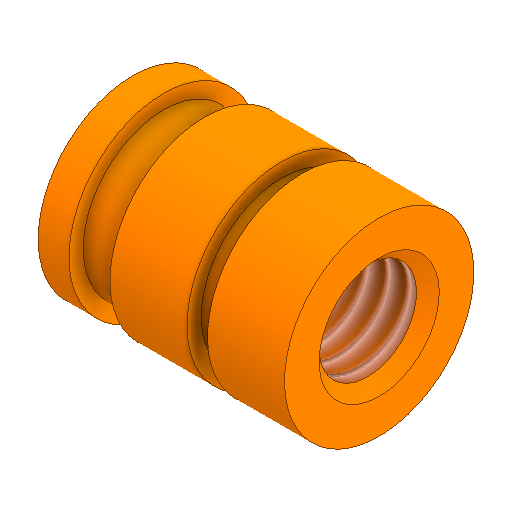
# Autodesk Inventor part: BN 1052 1386883 threaded insert for welding M4
Saved by Autodesk Inventor 2027 (Build 310192060, 192F)
## iProperties
Category: PARTsolutions
Company: BOSSARD
Created: 2025-05-08
Part Number: BN 1052 1386883 threaded insert for welding M4
Material: Generic
Catalog Web Link: www.cadenas.de
Description: BN 1052-Gewindeeinsätze zum Einschweissen für Ultraschallmontage, Messing, blank
Vendor: BOSSARD
Document SubType Name: Modeling
Designer: psAdmin
Manufacturer: BOSSARD
Mass: 0.168613 g
Surface Area: 3.16014 cm^2
Volume: 0.168613 cm^3
Density: 1 g/cm^3
Appearance: PSOLRGB-255-127-0
PSOL_IDENT_0: {$CADENAS_DATA/23d-libs/bossard/bossard_new/02/02_300/02_300_200/02_300_200_20/bn_1052/bn_1052.prj},
PSOL_IDENT_1: 253 {M=Nenngewinde},{VTYP=3D},{NB=BN 1052 1386883 threaded insert for welding M4},{LINA=BN 1052 1386
PSOL_IDENT_2: 883 threaded insert for welding M4},{NN=BN 1052},{DATE=22.04.2025 12:02:26},{GEOMDATE=26.01.2023 06:
PSOL_IDENT_3: 08:31},{VERSION=},{LINEID=210},{WBVAR=MAT},{WBNUMERIC=}  {NB=BN 1052 1386883 threaded insert for wel
PSOL_IDENT_4: ding M4},{LINA=BN 1052 1386883 threaded insert for welding M4},{KT=DUMMY},{NENN=M4},{CNSORDERNO=1386
PSOL_IDENT_5: 883},{BNARTNR=1386883},{BNNORM1=},{BNMAT=Messing},{CNSMAT=Messing},{BNSURFACE=blank},{GEW=M4},{D=4.0
PSOL_IDENT_6: 00},{P=0.700},{D1=3.242},{L=8.200},{D2=6.300},{MAT=},{D4=5.500},{D41=5.500},{D42=5.600},{A=2.500},{A
PSOL_IDENT_7: 1=2.500},{A2=2.100},{DIN962THREAD=}
NB: BN 1052 1386883 threaded insert for welding M4
NN: BN 1052
NT: Threaded inserts for ultrasonic installation, brass, plain
NBSYN: BN 1052 $BNARTNR. threaded insert for welding $NENN.$MAT.
LINA: BN 1052 1386883 threaded insert for welding M4
CATALOG: Bossard Catalog
ROWDESC: M4
BNARTNR: 1386883
BNMAT: Brass
BNSURFACE: plain
GEW: M4
D: 4
P: 0.7
D1: 3.242
L: 8.2
D2: 6.3
MAT: ABS
D4: 5.500
A: 2.500
SUPPLIER: BOSSARD
ARTICLENO: BN 1052 1386883 threaded insert for welding M4
BOMINFO: BN 1052 1386883 threaded insert for welding M4
CREATOR: CADENAS GmbH
Title: BN 1052 1386883 threaded insert for welding M4
Author: Cadenas PARTsolutions
Comments: Gewindeeinsätze zum Einschweissen für Ultraschallmontage, Messing, blank
Autodesk Inventor part; units mm, degrees
sketch "Sketch_1" plane through (0, 0, 0) normal (0, 0, 1) x (1, 0, 0)
  line L0 (8.2, 0) -> (0, 0)
  line L1 (0, 0) -> (0, 3.15)
  line L2 (0, 3.15) -> (1.025, 3.15)
  line L3 (1.025, 3.15) -> (1.025, 2.6775)
  line L4 (1.025, 2.6775) -> (2.3917, 2.6775)
  line L5 (2.3917, 2.6775) -> (2.3917, 3.15)
  line L6 (2.3917, 3.15) -> (4.9542, 3.15)
  line L7 (4.9542, 3.15) -> (4.9542, 2.6775)
  line L8 (4.9542, 2.6775) -> (5.6375, 2.6775)
  line L9 (5.6375, 2.6775) -> (5.6375, 3.15)
  line L10 (5.6375, 3.15) -> (8.2, 3.15)
  line L11 (8.2, 3.15) -> (8.2, 0)
  line L12 (8.2, 0) -> (0, 0)
  constraints: 26 end point
revolve "Revolution1" add sketch "Sketch_1" angle 360 about axis through (8.2, 0, 0) along (1, 0, 0)
sketch "Sketch_3" plane through (0, 0, 0) normal (0, 0, 1) x (1, 0, 0)
  line L0 (8.2, 0) -> (0, 0)
  line L1 (0, 0) -> (0, 2)
  line L2 (0, 2) -> (0.379, 1.621)
  line L3 (0.379, 1.621) -> (7.821, 1.621)
  line L4 (7.821, 1.621) -> (8.2, 2)
  line L5 (8.2, 2) -> (8.2, 0)
  line L6 (8.2, 0) -> (0, 0)
  constraints: 14 end point
revolve "Revolution2" cut sketch "Sketch_3" angle 360 about axis through (8.2, 0, 0) along (1, 0, 0)
thread "Thread1" size "M4x0.7" class "6H" standard "ISO Metric profile" full length
ref_plane "IP1_XY" through (0, 0, 0) normal (1, 0, 0) x (0, 0, -1)
ref_plane "IP1_YZ" through (0, 0, 0) normal (0, 0, -1) x (0, 1, 0)
ref_plane "IP1_ZX" through (0, 0, 0) normal (0, 1, 0) x (1, 0, 0)
ref_plane "IP2_XY" through (8.2, 0, 0) normal (1, 0, 0) x (0, 0, -1)
ref_plane "IP2_YZ" through (8.2, 0, 0) normal (0, 0, -1) x (0, 1, 0)
ref_plane "IP2_ZX" through (8.2, 0, 0) normal (0, 1, 0) x (1, 0, 0)
body "Solid1"
